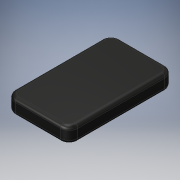
# Autodesk Inventor part: EAFU Battery
Saved by Autodesk Inventor 2019.4 (Build 234330000, 330)
## iProperties
Created: 2020-09-02
Part Number: EAFU Battery
Material: Generic
Document SubType Name: Modeling
Designer: Mike Angus
Density: 1 g/cm^3
Appearance: Glossy - Black
Author: Mike Angus
Autodesk Inventor part; units mm, degrees
ref_plane "YZ Plane" through (0, 0, 0) normal (1, 0, 0) x (0, 1, 0)
ref_plane "XZ Plane" through (0, 0, 0) normal (0, 1, 0) x (-1, 0, 0)
ref_plane "XY Plane" through (0, 0, 0) normal (0, 0, 1) x (1, 0, 0)
sketch "Sketch1" plane through (0, 0, 0) normal (0, 1, 0) x (-1, 0, 0)
  line L0 (32, 53.3) -> (-32, 53.3)
  line L1 (-32, 53.3) -> (-32, -53.3)
  line L2 (-32, -53.3) -> (32, -53.3)
  line L3 (32, -53.3) -> (32, 53.3)
  line L4 (32, 53.3) -> (-32, -53.3) construction
  line L5 (-32, 53.3) -> (32, -53.3) construction
  point P0 (0, 0)
  dimension "d0" = 64
  dimension "d1" = 106.6
  constraints: 12 end point, 2 midpoint, 2 parallel, 1 horizontal, 1 perpendicular
  measures "d0" distance of L2.end L1.end
  measures "d1" distance of L1.end L0.end
extrude "Extrusion1" add sketch "Sketch1" along normal blind 15.8
fillet "Fillet1" radius 9 4 edges at (32, 7.9, 53.3) (32, 7.9, -53.3) (-32, 7.9, 53.3) (-32, 7.9, -53.3)
fillet "Fillet1" radius 3.5 8 edges at (0, 15.8, 53.3) (32, 15.8, 0) (0, 15.8, -53.3) (-32, 15.8, 0) (0, 0, 53.3) (-32, 0, 0) (0, 0, -53.3) (32, 0, 0)
equation "\"d0\" = eb_width"
equation "\"d1\" = eb_length"
equation "\"d2\" = eb_depth"
equation "\"d4\" = eb_cornerFillets"
equation "\"d5\" = eb_edgeFillets"
equation "\"eb_length\" = 106.6"
equation "\"eb_width\" = 64"
equation "\"eb_depth\" = 15.8"
equation "\"eb_cornerFillets\" = 9"
equation "\"eb_edgeFillets\" = 3.5"
body "Solid1"
